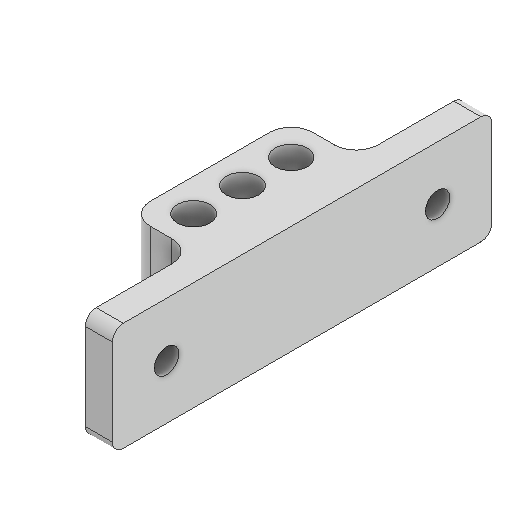
# Autodesk Inventor part: 3DP_PLA_Carbon_Rod_Holder_Top_REVB
Saved by Autodesk Inventor 2027 (Build 310192060, 192F)
## iProperties
Created: 2026-03-01
Part Number: 3DP_PLA_Carbon_Rod_Holder_Top_REVB
Material: Generic
Document SubType Name: Modeling
Designer: User
Density: 1 g/cm^3
Appearance: Default
Author: User
Autodesk Inventor part; units mm, degrees
ref_plane "YZ Plane" through (0, 0, 0) normal (1, 0, 0) x (0, 1, 0)
ref_plane "XZ Plane" through (0, 0, 0) normal (0, 1, 0) x (-1, 0, 0)
sketch "Sketch1" plane through (0, 0, 0) normal (0, 0, 1) x (1, 0, 0)
  line L0 (-5, 10) -> (0, 10)
  line L1 (0, 10) -> (0, -10)
  line L2 (0, -10) -> (-5, -10)
  line L3 (-5, -10) -> (-5, 10)
  point P0 (0, 0)
  point P1 (0, 0)
  dimension "d0" = 20
  dimension "d1" = 10
  dimension "d2" = 5
  constraints: 8 end point, 2 parallel, 1 horizontal, 1 midpoint, 1 perpendicular
  measures "d0" distance between parallel lines of L2 L0
  measures "d1" distance from line of point (0, 0) L0
  measures "d2" distance of L0.start L0.end
extrude "Extrusion1" add sketch "Sketch1" along normal blind 70
ref_plane "Work Plane1" through (0, 0, 20) normal (0, 0, -1) x (-1, 0, 0)
sketch "Sketch2" plane through (0, 0, 20) normal (0, 0, -1) x (-1, 0, 0)
  line L0 (5, -10) -> (0, -10) projected
  line L1 (0, -10) -> (0, 10) projected
  line L2 (0, 10) -> (5, 10) projected
  line L3 (5, 10) -> (5, -10) projected
  line L4 (5, 10) -> (17, 10)
  line L5 (17, 10) -> (17, -10)
  line L6 (17, -10) -> (5, -10)
  point P0 (0, 0)
  dimension "d6" = 12
  constraints: 6 end point, 2 perpendicular, 1 horizontal
  measures "d6" distance of L5.end L0.start
extrude "Extrusion2" add sketch "Sketch2" against normal blind 30 contours L3 L4 L5 L6
sketch "Sketch6" plane through (-5, -10, 70) normal (-1, 0, 0) x (0, 0, 1)
  line L0 (-50, 0) -> (-50, 20) projected
  line L1 (-70, 20) -> (-50, 20) projected
  line L2 (-70, 20) -> (-70, 0) projected
  line L3 (-70, 0) -> (-50, 0) projected
  line L4 (-20, 20) -> (-20, 0) projected
  line L5 (-20, 0) -> (0, 0) projected
  line L6 (0, 20) -> (0, 0) projected
  line L7 (-20, 20) -> (0, 20) projected
  point P0 (-70, 10)
  point P1 (-60, 10)
  point P2 (-10, 10)
  dimension "d26" = 20
  dimension "d27" = 20
  dimension "d28" = 10
  dimension "d29" = 10
  dimension "d30" = 10
  dimension "d31" = 10
  measures "d26" distance between parallel lines of L0 L2
  measures "d27" distance of L1.start L2.end
  measures "d28" distance from line of L2 point (-60, 10)
  measures "d29" distance from line of L3 point (-60, 10)
  measures "d30" distance from line of L5 point (-10, 10)
  measures "d31" distance from line of L6 point (-10, 10)
hole "Hole2" at (-5, 0, 10) at (-5, 0, 60) direction (1, 0, 0) diameter 4.5 end through all
fillet "Fillet1" radius 2 4 edges at (-2.5, 10, 70) (-2.5, -10, 70) (-2.5, -10, 0) (-2.5, 10, 0)
fillet "Fillet3" radius 4 2 edges at (-5, 0, 50) (-5, 0, 20)
sketch "Sketch7" plane through (-17, 10, 50) normal (0, 1, 0) x (1, 0, 0)
  line L0 (12, 48) -> (17, 48) projected
  line L1 (12, 48) -> (12, 34) projected
  arc A0 (8, 30) -> (12, 34) centre (8, 34) ccw projected
  line L2 (0, 30) -> (8, 30) projected
  line L3 (0, 30) -> (0, 0) projected
  line L4 (8, 0) -> (0, 0) projected
  arc A1 (12, -4) -> (8, 0) centre (8, -4) ccw projected
  line L5 (12, -4) -> (12, -18) projected
  line L6 (17, -18) -> (12, -18) projected
  line L7 (17, 48) -> (17, -18) projected
  circle A2 centre (6, 24) radius 3
  circle A3 centre (6, 15) radius 3
  circle A4 centre (6, 6) radius 3
  point P0 (17, 50)
  point P1 (4, 0)
  dimension "d42" = 6
  dimension "d43" = 6
  dimension "d44" = 6
  dimension "d45" = 30
  dimension "d46" = 6
  dimension "d47" = 9
  dimension "d48" = 9
  dimension "d50" = 6
  constraints: 3 centre point, 2 vertical alignment, 1 midpoint
  measures "d42" diameter of A2
  measures "d43" diameter of A3
  measures "d44" diameter of A4
  measures "d45" distance of L2.start L3.end
  measures "d46" distance from line of L2 A2.centre
  measures "d47" distance of A3.centre A2.centre
  measures "d48" distance of A3.centre A4.centre
  measures "d50" distance from line of L3 A2.centre
extrude "Extrusion4" cut sketch "Sketch7" against normal through all contours A2 | A3 | A4
fillet "Fillet4" radius 4 2 edges at (-17, 0, 20) (-17, 0, 50)
equation "\"d48\" = d47"
body "Solid1"
